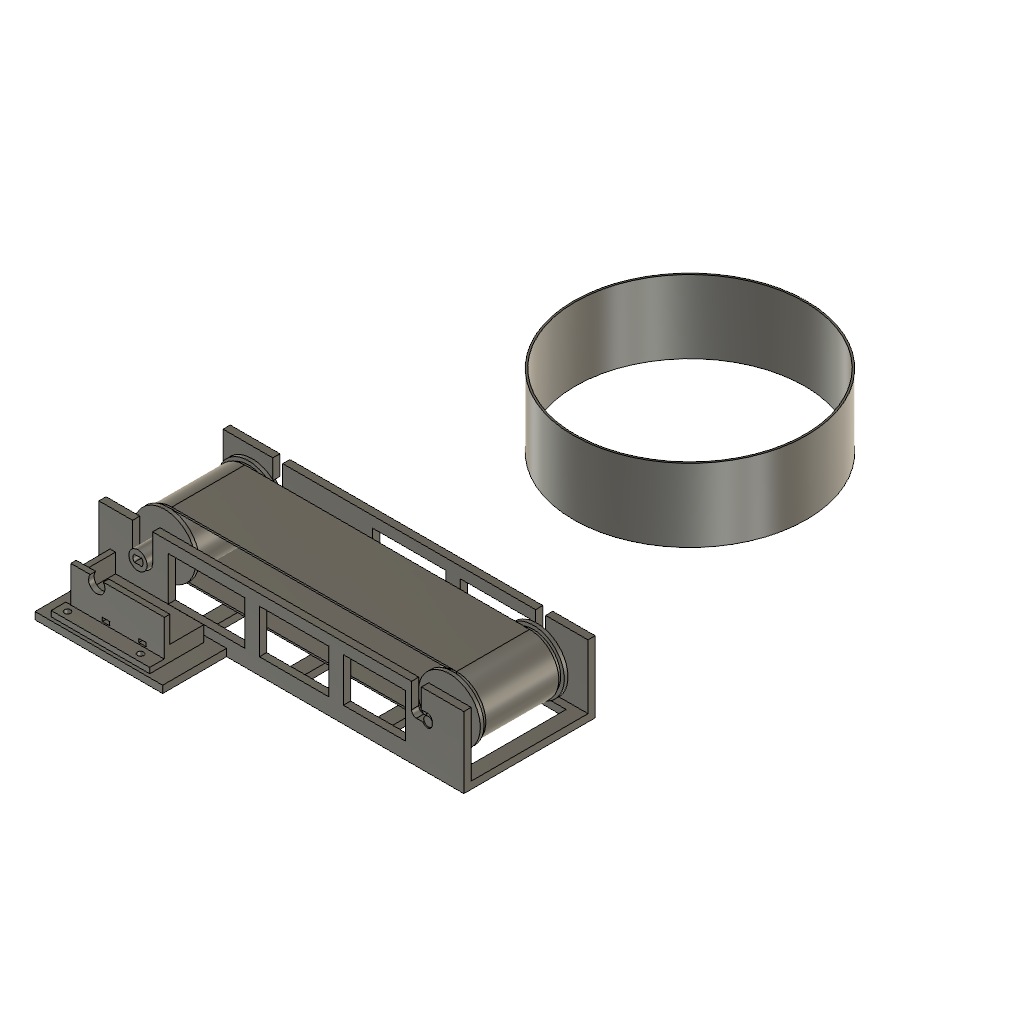
effente_conveyor (Autodesk Fusion 360 design; units mm, degrees)
part number: 2026-11-16-22-43-14-375
part number: 2026-11-16-22-43-14-555
part number: 2026-11-16-22-43-15-249
part number: 2026-11-16-22-43-15-701
part number: 2026-11-16-22-43-16-000
part number: 2026-11-16-22-43-16-313
part number: 2026-11-16-22-43-16-414
Autodesk Fusion 360 part; units mm, degrees
sketch "Sketch1" plane through (0, 0, 0) normal (0, 0, 1) x (1, 0, 0) in component "Frame"
  line L0 (0, 0) -> (200, 0)
  line L1 (200, 0) -> (200, 72)
  line L2 (200, 72) -> (0, 72)
  line L3 (0, 72) -> (0, 0)
extrude "Extrude1" add sketch "Sketch1" along normal blind 4 makes body 1 in component "Frame"
ref_plane "WorkPlane1" through (0, 0, 4) normal (0, 0, 1) x (1, 0, 0) in component "Frame"
sketch "Sketch2" plane through (0, 0, 4) normal (0, 0, 1) x (1, 0, 0) in component "Frame"
  line L0 (0, 0) -> (200, 0)
  line L1 (200, 0) -> (200, 4)
  line L2 (200, 4) -> (0, 4)
  line L3 (0, 4) -> (0, 0)
extrude "Extrude2" add sketch "Sketch2" along normal blind 35 bodies 1 in component "Frame"
ref_plane "WorkPlane2" through (0, 0, 4) normal (0, 0, 1) x (1, 0, 0) in component "Frame"
sketch "Sketch3" plane through (0, 0, 4) normal (0, 0, 1) x (1, 0, 0) in component "Frame"
  line L0 (0, 68) -> (200, 68)
  line L1 (200, 68) -> (200, 72)
  line L2 (200, 72) -> (0, 72)
  line L3 (0, 72) -> (0, 68)
extrude "Extrude3" add sketch "Sketch3" along normal blind 35 bodies 1 in component "Frame"
sketch "Sketch4" plane through (0, 0, 0) normal (0, 0, 1) x (1, 0, 0) in component "Frame"
  line L0 (0, -35) -> (70, -35)
  line L1 (70, -35) -> (70, 0.5)
  line L2 (70, 0.5) -> (0, 0.5)
  line L3 (0, 0.5) -> (0, -35)
extrude "Extrude4" add sketch "Sketch4" along normal blind 4 bodies 1 in component "Frame"
ref_plane "WorkPlane3" through (0, 2, 0) normal (0, 1, 0) x (0, 0, 1) in component "Frame"
sketch "Sketch5" plane through (0, 2, 0) normal (0, 1, 0) x (1, 0, 0) in component "Frame"
  line L0 (38, -9) -> (80, -9)
  line L1 (80, -9) -> (80, -33)
  line L2 (80, -33) -> (38, -33)
  line L3 (38, -33) -> (38, -9)
extrude "Extrude5" cut sketch "Sketch5" along normal mid plane 5 bodies 1 in component "Frame"
ref_plane "WorkPlane4" through (0, 2, 0) normal (0, 1, 0) x (0, 0, 1) in component "Frame"
sketch "Sketch6" plane through (0, 2, 0) normal (0, 1, 0) x (1, 0, 0) in component "Frame"
  line L0 (88, -9) -> (126, -9)
  line L1 (126, -9) -> (126, -33)
  line L2 (126, -33) -> (88, -33)
  line L3 (88, -33) -> (88, -9)
extrude "Extrude6" cut sketch "Sketch6" along normal mid plane 5 bodies 1 in component "Frame"
ref_plane "WorkPlane5" through (0, 2, 0) normal (0, 1, 0) x (0, 0, 1) in component "Frame"
sketch "Sketch7" plane through (0, 2, 0) normal (0, 1, 0) x (1, 0, 0) in component "Frame"
  line L0 (134, -9) -> (168, -9)
  line L1 (168, -9) -> (168, -33)
  line L2 (168, -33) -> (134, -33)
  line L3 (134, -33) -> (134, -9)
extrude "Extrude7" cut sketch "Sketch7" along normal mid plane 5 bodies 1 in component "Frame"
ref_plane "WorkPlane6" through (0, 70, 0) normal (0, 1, 0) x (0, 0, 1) in component "Frame"
sketch "Sketch8" plane through (0, 70, 0) normal (0, 1, 0) x (1, 0, 0) in component "Frame"
  line L0 (82, -9) -> (122, -9)
  line L1 (122, -9) -> (122, -33)
  line L2 (122, -33) -> (82, -33)
  line L3 (82, -33) -> (82, -9)
extrude "Extrude8" cut sketch "Sketch8" along normal mid plane 5 bodies 1 in component "Frame"
ref_plane "WorkPlane7" through (0, 70, 0) normal (0, 1, 0) x (0, 0, 1) in component "Frame"
sketch "Sketch9" plane through (0, 70, 0) normal (0, 1, 0) x (1, 0, 0) in component "Frame"
  line L0 (130, -9) -> (168, -9)
  line L1 (168, -9) -> (168, -33)
  line L2 (168, -33) -> (130, -33)
  line L3 (130, -33) -> (130, -9)
extrude "Extrude9" cut sketch "Sketch9" along normal mid plane 5 bodies 1 in component "Frame"
ref_plane "WorkPlane8" through (0, 0, -0.5) normal (0, 0, 1) x (1, 0, 0) in component "Frame"
sketch "Sketch10" plane through (0, 0, -0.5) normal (0, 0, 1) x (1, 0, 0) in component "Frame"
  line L0 (8, 8) -> (48, 8)
  line L1 (48, 8) -> (48, 64)
  line L2 (48, 64) -> (8, 64)
  line L3 (8, 64) -> (8, 8)
extrude "Extrude10" cut sketch "Sketch10" along normal blind 5 bodies 1 in component "Frame"
ref_plane "WorkPlane9" through (0, 0, -0.5) normal (0, 0, 1) x (1, 0, 0) in component "Frame"
sketch "Sketch11" plane through (0, 0, -0.5) normal (0, 0, 1) x (1, 0, 0) in component "Frame"
  line L0 (56, 8) -> (96, 8)
  line L1 (96, 8) -> (96, 64)
  line L2 (96, 64) -> (56, 64)
  line L3 (56, 64) -> (56, 8)
extrude "Extrude11" cut sketch "Sketch11" along normal blind 5 bodies 1 in component "Frame"
ref_plane "WorkPlane10" through (0, 0, -0.5) normal (0, 0, 1) x (1, 0, 0) in component "Frame"
sketch "Sketch12" plane through (0, 0, -0.5) normal (0, 0, 1) x (1, 0, 0) in component "Frame"
  line L0 (104, 8) -> (144, 8)
  line L1 (144, 8) -> (144, 64)
  line L2 (144, 64) -> (104, 64)
  line L3 (104, 64) -> (104, 8)
extrude "Extrude12" cut sketch "Sketch12" along normal blind 5 bodies 1 in component "Frame"
ref_plane "WorkPlane11" through (0, 0, -0.5) normal (0, 0, 1) x (1, 0, 0) in component "Frame"
sketch "Sketch13" plane through (0, 0, -0.5) normal (0, 0, 1) x (1, 0, 0) in component "Frame"
  line L0 (152, 8) -> (192, 8)
  line L1 (192, 8) -> (192, 64)
  line L2 (192, 64) -> (152, 64)
  line L3 (152, 64) -> (152, 8)
extrude "Extrude13" cut sketch "Sketch13" along normal blind 5 bodies 1 in component "Frame"
ref_plane "WorkPlane12" through (0, 70, 0) normal (0, 1, 0) x (0, 0, 1) in component "Frame"
sketch "Sketch14" plane through (0, 70, 0) normal (0, 1, 0) x (1, 0, 0) in component "Frame"
  circle A0 centre (24, -24) radius 2.7
extrude "Extrude14" cut sketch "Sketch14" along normal mid plane 5 bodies 1 in component "Frame"
ref_plane "WorkPlane13" through (0, 70, 0) normal (0, 1, 0) x (0, 0, 1) in component "Frame"
sketch "Sketch15" plane through (0, 70, 0) normal (0, 1, 0) x (1, 0, 0) in component "Frame"
  line L0 (24, -22.8) -> (30, -22.8)
  line L1 (30, -22.8) -> (30, -28.2)
  line L2 (30, -28.2) -> (24, -28.2)
  line L3 (24, -28.2) -> (24, -22.8)
extrude "Extrude15" cut sketch "Sketch15" along normal mid plane 5 bodies 1 in component "Frame"
ref_plane "WorkPlane14" through (0, 70, 0) normal (0, 1, 0) x (0, 0, 1) in component "Frame"
sketch "Sketch16" plane through (0, 70, 0) normal (0, 1, 0) x (1, 0, 0) in component "Frame"
  circle A0 centre (24, -25.5) radius 2.7
extrude "Extrude16" cut sketch "Sketch16" along normal mid plane 5 bodies 1 in component "Frame"
ref_plane "WorkPlane15" through (0, 70, 0) normal (0, 1, 0) x (0, 0, 1) in component "Frame"
sketch "Sketch17" plane through (0, 70, 0) normal (0, 1, 0) x (1, 0, 0) in component "Frame"
  circle A0 centre (30, -25.5) radius 2.7
extrude "Extrude17" cut sketch "Sketch17" along normal mid plane 5 bodies 1 in component "Frame"
ref_plane "WorkPlane16" through (0, 70, 0) normal (0, 1, 0) x (0, 0, 1) in component "Frame"
sketch "Sketch18" plane through (0, 70, 0) normal (0, 1, 0) x (1, 0, 0) in component "Frame"
  line L0 (27.3, -25.5) -> (32.7, -25.5)
  line L1 (32.7, -25.5) -> (32.7, -40)
  line L2 (32.7, -40) -> (27.3, -40)
  line L3 (27.3, -40) -> (27.3, -25.5)
extrude "Extrude18" cut sketch "Sketch18" along normal mid plane 5 bodies 1 in component "Frame"
ref_plane "WorkPlane17" through (0, 2, 0) normal (0, 1, 0) x (0, 0, 1) in component "Frame"
sketch "Sketch19" plane through (0, 2, 0) normal (0, 1, 0) x (1, 0, 0) in component "Frame"
  circle A0 centre (180, -24) radius 2.7
extrude "Extrude19" cut sketch "Sketch19" along normal mid plane 5 bodies 1 in component "Frame"
ref_plane "WorkPlane18" through (0, 2, 0) normal (0, 1, 0) x (0, 0, 1) in component "Frame"
sketch "Sketch20" plane through (0, 2, 0) normal (0, 1, 0) x (1, 0, 0) in component "Frame"
  line L0 (174, -22.8) -> (180, -22.8)
  line L1 (180, -22.8) -> (180, -28.2)
  line L2 (180, -28.2) -> (174, -28.2)
  line L3 (174, -28.2) -> (174, -22.8)
extrude "Extrude20" cut sketch "Sketch20" along normal mid plane 5 bodies 1 in component "Frame"
ref_plane "WorkPlane19" through (0, 2, 0) normal (0, 1, 0) x (0, 0, 1) in component "Frame"
sketch "Sketch21" plane through (0, 2, 0) normal (0, 1, 0) x (1, 0, 0) in component "Frame"
  circle A0 centre (180, -25.5) radius 2.7
extrude "Extrude21" cut sketch "Sketch21" along normal mid plane 5 bodies 1 in component "Frame"
ref_plane "WorkPlane20" through (0, 2, 0) normal (0, 1, 0) x (0, 0, 1) in component "Frame"
sketch "Sketch22" plane through (0, 2, 0) normal (0, 1, 0) x (1, 0, 0) in component "Frame"
  circle A0 centre (174, -25.5) radius 2.7
extrude "Extrude22" cut sketch "Sketch22" along normal mid plane 5 bodies 1 in component "Frame"
ref_plane "WorkPlane21" through (0, 2, 0) normal (0, 1, 0) x (0, 0, 1) in component "Frame"
sketch "Sketch23" plane through (0, 2, 0) normal (0, 1, 0) x (1, 0, 0) in component "Frame"
  line L0 (171.3, -25.5) -> (176.7, -25.5)
  line L1 (176.7, -25.5) -> (176.7, -40)
  line L2 (176.7, -40) -> (171.3, -40)
  line L3 (171.3, -40) -> (171.3, -25.5)
extrude "Extrude23" cut sketch "Sketch23" along normal mid plane 5 bodies 1 in component "Frame"
ref_plane "WorkPlane22" through (0, 70, 0) normal (0, 1, 0) x (0, 0, 1) in component "Frame"
sketch "Sketch24" plane through (0, 70, 0) normal (0, 1, 0) x (1, 0, 0) in component "Frame"
  circle A0 centre (180, -24) radius 2.7
extrude "Extrude24" cut sketch "Sketch24" along normal mid plane 5 bodies 1 in component "Frame"
ref_plane "WorkPlane23" through (0, 70, 0) normal (0, 1, 0) x (0, 0, 1) in component "Frame"
sketch "Sketch25" plane through (0, 70, 0) normal (0, 1, 0) x (1, 0, 0) in component "Frame"
  line L0 (174, -22.8) -> (180, -22.8)
  line L1 (180, -22.8) -> (180, -28.2)
  line L2 (180, -28.2) -> (174, -28.2)
  line L3 (174, -28.2) -> (174, -22.8)
extrude "Extrude25" cut sketch "Sketch25" along normal mid plane 5 bodies 1 in component "Frame"
ref_plane "WorkPlane24" through (0, 70, 0) normal (0, 1, 0) x (0, 0, 1) in component "Frame"
sketch "Sketch26" plane through (0, 70, 0) normal (0, 1, 0) x (1, 0, 0) in component "Frame"
  circle A0 centre (180, -25.5) radius 2.7
extrude "Extrude26" cut sketch "Sketch26" along normal mid plane 5 bodies 1 in component "Frame"
ref_plane "WorkPlane25" through (0, 70, 0) normal (0, 1, 0) x (0, 0, 1) in component "Frame"
sketch "Sketch27" plane through (0, 70, 0) normal (0, 1, 0) x (1, 0, 0) in component "Frame"
  circle A0 centre (174, -25.5) radius 2.7
extrude "Extrude27" cut sketch "Sketch27" along normal mid plane 5 bodies 1 in component "Frame"
ref_plane "WorkPlane26" through (0, 70, 0) normal (0, 1, 0) x (0, 0, 1) in component "Frame"
sketch "Sketch28" plane through (0, 70, 0) normal (0, 1, 0) x (1, 0, 0) in component "Frame"
  line L0 (171.3, -25.5) -> (176.7, -25.5)
  line L1 (176.7, -25.5) -> (176.7, -40)
  line L2 (176.7, -40) -> (171.3, -40)
  line L3 (171.3, -40) -> (171.3, -25.5)
extrude "Extrude28" cut sketch "Sketch28" along normal mid plane 5 bodies 1 in component "Frame"
ref_plane "WorkPlane27" through (0, 2, 0) normal (0, 1, 0) x (0, 0, 1) in component "Frame"
sketch "Sketch29" plane through (0, 2, 0) normal (0, 1, 0) x (1, 0, 0) in component "Frame"
  line L0 (18.5, -24) -> (29.5, -24)
  line L1 (29.5, -24) -> (29.5, -40)
  line L2 (29.5, -40) -> (18.5, -40)
  line L3 (18.5, -40) -> (18.5, -24)
extrude "Extrude29" cut sketch "Sketch29" along normal mid plane 5 bodies 1 in component "Frame"
ref_plane "WorkPlane28" through (0, 2, 0) normal (0, 1, 0) x (0, 0, 1) in component "Frame"
sketch "Sketch30" plane through (0, 2, 0) normal (0, 1, 0) x (1, 0, 0) in component "Frame"
  circle A0 centre (24, -24) radius 5.5
extrude "Extrude30" cut sketch "Sketch30" along normal mid plane 5 bodies 1 in component "Frame"
ref_plane "WorkPlane29" through (0, 0, -0.5) normal (0, 0, 1) x (1, 0, 0) in component "Frame"
sketch "Sketch31" plane through (0, 0, -0.5) normal (0, 0, 1) x (1, 0, 0) in component "Frame"
  circle A0 centre (12, -29.1) radius 1.7
extrude "Extrude31" cut sketch "Sketch31" along normal blind 5 bodies 1 in component "Frame"
ref_plane "WorkPlane30" through (0, 0, -0.5) normal (0, 0, 1) x (1, 0, 0) in component "Frame"
sketch "Sketch32" plane through (0, 0, -0.5) normal (0, 0, 1) x (1, 0, 0) in component "Frame"
  line L0 (15.2332, -29.1) -> (13.6166, -26.3)
  line L1 (13.6166, -26.3) -> (10.3834, -26.3)
  line L2 (10.3834, -26.3) -> (8.7668, -29.1)
  line L3 (8.7668, -29.1) -> (10.3834, -31.9)
  line L4 (10.3834, -31.9) -> (13.6166, -31.9)
  line L5 (13.6166, -31.9) -> (15.2332, -29.1)
extrude "Extrude32" cut sketch "Sketch32" along normal blind 3 bodies 1 in component "Frame"
ref_plane "WorkPlane31" through (0, 0, -0.5) normal (0, 0, 1) x (1, 0, 0) in component "Frame"
sketch "Sketch33" plane through (0, 0, -0.5) normal (0, 0, 1) x (1, 0, 0) in component "Frame"
  circle A0 centre (52, -29.1) radius 1.7
extrude "Extrude33" cut sketch "Sketch33" along normal blind 5 bodies 1 in component "Frame"
ref_plane "WorkPlane32" through (0, 0, -0.5) normal (0, 0, 1) x (1, 0, 0) in component "Frame"
sketch "Sketch34" plane through (0, 0, -0.5) normal (0, 0, 1) x (1, 0, 0) in component "Frame"
  line L0 (55.2332, -29.1) -> (53.6166, -26.3)
  line L1 (53.6166, -26.3) -> (50.3834, -26.3)
  line L2 (50.3834, -26.3) -> (48.7668, -29.1)
  line L3 (48.7668, -29.1) -> (50.3834, -31.9)
  line L4 (50.3834, -31.9) -> (53.6166, -31.9)
  line L5 (53.6166, -31.9) -> (55.2332, -29.1)
extrude "Extrude34" cut sketch "Sketch34" along normal blind 3 bodies 1 in component "Frame"
ref_plane "WorkPlane33" through (0, 71.25, 0) normal (0, 1, 0) x (0, 0, 1) in component "Frame"
sketch "Sketch35" plane through (0, 71.25, 0) normal (0, 1, 0) x (1, 0, 0) in component "Frame"
  circle A0 centre (60, -24) radius 10.05
extrude "Extrude35" cut sketch "Sketch35" along normal mid plane 2.5 bodies 1 in component "Frame"
ref_plane "WorkPlane1" through (0, 36, 0) normal (0, 1, 0) x (0, 0, 1) in component "Drive roller"
sketch "Sketch1 (2)" plane through (0, 36, 0) normal (0, 1, 0) x (1, 0, 0) in component "Drive roller"
  circle A0 centre (24, -24) radius 15
extrude "Extrude1'" add sketch "Sketch1 (2)" along normal mid plane 44 separate body makes body 2 in component "Drive roller"
ref_plane "WorkPlane2" through (0, 13, 0) normal (0, 1, 0) x (0, 0, 1) in component "Drive roller"
sketch "Sketch2 (2)" plane through (0, 13, 0) normal (0, 1, 0) x (1, 0, 0) in component "Drive roller"
  circle A0 centre (24, -24) radius 17
extrude "Extrude2'" add sketch "Sketch2 (2)" along normal mid plane 2 bodies 2 in component "Drive roller"
ref_plane "WorkPlane3" through (0, 59, 0) normal (0, 1, 0) x (0, 0, 1) in component "Drive roller"
sketch "Sketch3 (2)" plane through (0, 59, 0) normal (0, 1, 0) x (1, 0, 0) in component "Drive roller"
  circle A0 centre (24, -24) radius 17
extrude "Extrude3'" add sketch "Sketch3 (2)" along normal mid plane 2 bodies 2 in component "Drive roller"
ref_plane "WorkPlane4" through (0, 63.75, 0) normal (0, 1, 0) x (0, 0, 1) in component "Drive roller"
sketch "Sketch4 (2)" plane through (0, 63.75, 0) normal (0, 1, 0) x (1, 0, 0) in component "Drive roller"
  circle A0 centre (24, -24) radius 5
extrude "Extrude4'" add sketch "Sketch4 (2)" along normal mid plane 7.5 bodies 2 in component "Drive roller"
ref_plane "WorkPlane5" through (0, 69.5, 0) normal (0, 1, 0) x (0, 0, 1) in component "Drive roller"
sketch "Sketch5 (2)" plane through (0, 69.5, 0) normal (0, 1, 0) x (1, 0, 0) in component "Drive roller"
  circle A0 centre (24, -24) radius 2.5
extrude "Extrude5'" add sketch "Sketch5 (2)" along normal mid plane 4 bodies 2 in component "Drive roller"
ref_plane "WorkPlane6" through (0, 4.75, 0) normal (0, 1, 0) x (0, 0, 1) in component "Drive roller"
sketch "Sketch6 (2)" plane through (0, 4.75, 0) normal (0, 1, 0) x (1, 0, 0) in component "Drive roller"
  circle A0 centre (24, -24) radius 5
extrude "Extrude6'" add sketch "Sketch6 (2)" along normal mid plane 14.5 bodies 2 in component "Drive roller"
ref_plane "WorkPlane7" through (0, 1.5, 0) normal (0, 1, 0) x (0, 0, 1) in component "Drive roller"
sketch "Sketch7 (2)" plane through (0, 1.5, 0) normal (0, 1, 0) x (1, 0, 0) in component "Drive roller"
  circle A0 centre (24, -24) radius 2.8
extrude "Extrude7'" cut sketch "Sketch7 (2)" along normal mid plane 9 bodies 2 in component "Drive roller"
ref_plane "WorkPlane8" through (0, 1.75, 0) normal (0, 1, 0) x (0, 0, 1) in component "Drive roller"
sketch "Sketch8 (2)" plane through (0, 1.75, 0) normal (0, 1, 0) x (1, 0, 0) in component "Drive roller"
  line L0 (20.9, -25.925) -> (27.1, -25.925)
  line L1 (27.1, -25.925) -> (27.1, -27.1)
  line L2 (27.1, -27.1) -> (20.9, -27.1)
  line L3 (20.9, -27.1) -> (20.9, -25.925)
extrude "Extrude8'" add sketch "Sketch8 (2)" along normal mid plane 8.5 bodies 2 in component "Drive roller"
ref_plane "WorkPlane9" through (0, 1.75, 0) normal (0, 1, 0) x (0, 0, 1) in component "Drive roller"
sketch "Sketch9 (2)" plane through (0, 1.75, 0) normal (0, 1, 0) x (1, 0, 0) in component "Drive roller"
  line L0 (20.9, -20.9) -> (27.1, -20.9)
  line L1 (27.1, -20.9) -> (27.1, -22.075)
  line L2 (27.1, -22.075) -> (20.9, -22.075)
  line L3 (20.9, -22.075) -> (20.9, -20.9)
extrude "Extrude9'" add sketch "Sketch9 (2)" along normal mid plane 8.5 bodies 2 in component "Drive roller"
ref_plane "WorkPlane10" through (0, 56.25, 0) normal (0, 1, 0) x (0, 0, 1) in component "Drive roller"
sketch "Sketch10 (2)" plane through (0, 56.25, 0) normal (0, 1, 0) x (1, 0, 0) in component "Drive roller"
  circle A0 centre (34, -24) radius 1.3
extrude "Extrude10'" cut sketch "Sketch10 (2)" along normal mid plane 8.5 bodies 2 in component "Drive roller"
ref_plane "WorkPlane11" through (0, 56.25, 0) normal (0, 1, 0) x (0, 0, 1) in component "Drive roller"
sketch "Sketch11 (2)" plane through (0, 56.25, 0) normal (0, 1, 0) x (1, 0, 0) in component "Drive roller"
  circle A0 centre (24, -34) radius 1.3
extrude "Extrude11'" cut sketch "Sketch11 (2)" along normal mid plane 8.5 bodies 2 in component "Drive roller"
ref_plane "WorkPlane12" through (0, 56.25, 0) normal (0, 1, 0) x (0, 0, 1) in component "Drive roller"
sketch "Sketch12 (2)" plane through (0, 56.25, 0) normal (0, 1, 0) x (1, 0, 0) in component "Drive roller"
  circle A0 centre (14, -24) radius 1.3
extrude "Extrude12'" cut sketch "Sketch12 (2)" along normal mid plane 8.5 bodies 2 in component "Drive roller"
ref_plane "WorkPlane13" through (0, 56.25, 0) normal (0, 1, 0) x (0, 0, 1) in component "Drive roller"
sketch "Sketch13 (2)" plane through (0, 56.25, 0) normal (0, 1, 0) x (1, 0, 0) in component "Drive roller"
  circle A0 centre (24, -14) radius 1.3
extrude "Extrude13'" cut sketch "Sketch13 (2)" along normal mid plane 8.5 bodies 2 in component "Drive roller"
ref_plane "WorkPlane1" through (0, 36, 0) normal (0, 1, 0) x (0, 0, 1) in component "Idle roller"
sketch "Sketch1 (3)" plane through (0, 36, 0) normal (0, 1, 0) x (1, 0, 0) in component "Idle roller"
  circle A0 centre (180, -24) radius 15
extrude "Extrude1''" add sketch "Sketch1 (3)" along normal mid plane 44 separate body makes body 3 in component "Idle roller"
ref_plane "WorkPlane2" through (0, 13, 0) normal (0, 1, 0) x (0, 0, 1) in component "Idle roller"
sketch "Sketch2 (3)" plane through (0, 13, 0) normal (0, 1, 0) x (1, 0, 0) in component "Idle roller"
  circle A0 centre (180, -24) radius 17
extrude "Extrude2''" add sketch "Sketch2 (3)" along normal mid plane 2 bodies 3 in component "Idle roller"
ref_plane "WorkPlane3" through (0, 59, 0) normal (0, 1, 0) x (0, 0, 1) in component "Idle roller"
sketch "Sketch3 (3)" plane through (0, 59, 0) normal (0, 1, 0) x (1, 0, 0) in component "Idle roller"
  circle A0 centre (180, -24) radius 17
extrude "Extrude3''" add sketch "Sketch3 (3)" along normal mid plane 2 bodies 3 in component "Idle roller"
ref_plane "WorkPlane4" through (0, 63.75, 0) normal (0, 1, 0) x (0, 0, 1) in component "Idle roller"
sketch "Sketch4 (3)" plane through (0, 63.75, 0) normal (0, 1, 0) x (1, 0, 0) in component "Idle roller"
  circle A0 centre (180, -24) radius 5
extrude "Extrude4''" add sketch "Sketch4 (3)" along normal mid plane 7.5 bodies 3 in component "Idle roller"
ref_plane "WorkPlane5" through (0, 69.5, 0) normal (0, 1, 0) x (0, 0, 1) in component "Idle roller"
sketch "Sketch5 (3)" plane through (0, 69.5, 0) normal (0, 1, 0) x (1, 0, 0) in component "Idle roller"
  circle A0 centre (180, -24) radius 2.5
extrude "Extrude5''" add sketch "Sketch5 (3)" along normal mid plane 4 bodies 3 in component "Idle roller"
ref_plane "WorkPlane6" through (0, 8.25, 0) normal (0, 1, 0) x (0, 0, 1) in component "Idle roller"
sketch "Sketch6 (3)" plane through (0, 8.25, 0) normal (0, 1, 0) x (1, 0, 0) in component "Idle roller"
  circle A0 centre (180, -24) radius 5
extrude "Extrude6''" add sketch "Sketch6 (3)" along normal mid plane 7.5 bodies 3 in component "Idle roller"
ref_plane "WorkPlane7" through (0, 2.5, 0) normal (0, 1, 0) x (0, 0, 1) in component "Idle roller"
sketch "Sketch7 (3)" plane through (0, 2.5, 0) normal (0, 1, 0) x (1, 0, 0) in component "Idle roller"
  circle A0 centre (180, -24) radius 2.5
extrude "Extrude7''" add sketch "Sketch7 (3)" along normal mid plane 4 bodies 3 in component "Idle roller"
ref_plane "WorkPlane1" through (0, 36, 0) normal (0, 1, 0) x (0, 0, 1) in component "Belt (reference)"
sketch "Sketch1 (4)" plane through (0, 36, 0) normal (0, 1, 0) x (1, 0, 0) in component "Belt (reference)"
  circle A0 centre (24, -24) radius 16
extrude "Extrude1'''" add sketch "Sketch1 (4)" along normal mid plane 40 separate body makes body 4 in component "Belt (reference)"
ref_plane "WorkPlane2" through (0, 36, 0) normal (0, 1, 0) x (0, 0, 1) in component "Belt (reference)"
sketch "Sketch2 (4)" plane through (0, 36, 0) normal (0, 1, 0) x (1, 0, 0) in component "Belt (reference)"
  circle A0 centre (180, -24) radius 16
extrude "Extrude2'''" add sketch "Sketch2 (4)" along normal mid plane 40 bodies 4 makes body 5 in component "Belt (reference)"
ref_plane "WorkPlane3" through (0, 36, 0) normal (0, 1, 0) x (0, 0, 1) in component "Belt (reference)"
sketch "Sketch3 (4)" plane through (0, 36, 0) normal (0, 1, 0) x (1, 0, 0) in component "Belt (reference)"
  line L0 (24, -8) -> (180, -8)
  line L1 (180, -8) -> (180, -40)
  line L2 (180, -40) -> (24, -40)
  line L3 (24, -40) -> (24, -8)
extrude "Extrude3'''" add sketch "Sketch3 (4)" along normal mid plane 40 bodies 4 in component "Belt (reference)"
ref_plane "WorkPlane4" through (0, 36, 0) normal (0, 1, 0) x (0, 0, 1) in component "Belt (reference)"
sketch "Sketch4 (4)" plane through (0, 36, 0) normal (0, 1, 0) x (1, 0, 0) in component "Belt (reference)"
  circle A0 centre (24, -24) radius 15
extrude "Extrude4'''" cut sketch "Sketch4 (4)" along normal mid plane 42 bodies 4 in component "Belt (reference)"
ref_plane "WorkPlane5" through (0, 36, 0) normal (0, 1, 0) x (0, 0, 1) in component "Belt (reference)"
sketch "Sketch5 (4)" plane through (0, 36, 0) normal (0, 1, 0) x (1, 0, 0) in component "Belt (reference)"
  circle A0 centre (180, -24) radius 15
extrude "Extrude5'''" cut sketch "Sketch5 (4)" along normal mid plane 42 bodies 4 in component "Belt (reference)"
ref_plane "WorkPlane6" through (0, 36, 0) normal (0, 1, 0) x (0, 0, 1) in component "Belt (reference)"
sketch "Sketch6 (4)" plane through (0, 36, 0) normal (0, 1, 0) x (1, 0, 0) in component "Belt (reference)"
  line L0 (24, -9) -> (180, -9)
  line L1 (180, -9) -> (180, -39)
  line L2 (180, -39) -> (24, -39)
  line L3 (24, -39) -> (24, -9)
extrude "Extrude6'''" cut sketch "Sketch6 (4)" along normal mid plane 42 bodies 4 in component "Belt (reference)"
sketch "Sketch1 (5)" plane through (0, 0, 0) normal (0, 0, 1) x (1, 0, 0) in component "Belt (TPU print)"
  circle A0 centre (100, 223.8532) radius 63.8532
extrude "Extrude1''''" add sketch "Sketch1 (5)" along normal blind 40 separate body makes body 6 in component "Belt (TPU print)"
ref_plane "WorkPlane1" through (0, 0, -0.5) normal (0, 0, 1) x (1, 0, 0) in component "Belt (TPU print)"
sketch "Sketch2 (5)" plane through (0, 0, -0.5) normal (0, 0, 1) x (1, 0, 0) in component "Belt (TPU print)"
  circle A0 centre (100, 223.8532) radius 62.8532
extrude "Extrude2''''" cut sketch "Sketch2 (5)" along normal blind 41 bodies 6 in component "Belt (TPU print)"
ref_plane "WorkPlane1" through (0, 0, 4) normal (0, 0, 1) x (1, 0, 0) in component "Motor bracket"
sketch "Sketch1 (6)" plane through (0, 0, 4) normal (0, 0, 1) x (1, 0, 0) in component "Motor bracket"
  line L0 (9.7, -33.1) -> (61, -33.1)
  line L1 (61, -33.1) -> (61, -3.5)
  line L2 (61, -3.5) -> (9.7, -3.5)
  line L3 (9.7, -3.5) -> (9.7, -33.1)
extrude "Extrude1'''''" add sketch "Sketch1 (6)" along normal blind 3 separate body makes body 7 in component "Motor bracket"
ref_plane "WorkPlane2" through (0, 0, 4) normal (0, 0, 1) x (1, 0, 0) in component "Motor bracket"
sketch "Sketch2 (6)" plane through (0, 0, 4) normal (0, 0, 1) x (1, 0, 0) in component "Motor bracket"
  line L0 (7, -33.1) -> (57, -33.1)
  line L1 (57, -33.1) -> (57, -25.09)
  line L2 (57, -25.09) -> (7, -25.09)
  line L3 (7, -25.09) -> (7, -33.1)
extrude "Extrude2'''''" add sketch "Sketch2 (6)" along normal blind 3 bodies 7 in component "Motor bracket"
ref_plane "WorkPlane3" through (0, 0, 6.99) normal (0, 0, 1) x (1, 0, 0) in component "Motor bracket"
sketch "Sketch3 (5)" plane through (0, 0, 6.99) normal (0, 0, 1) x (1, 0, 0) in component "Motor bracket"
  line L0 (12.7, -22.11) -> (61, -22.11)
  line L1 (61, -22.11) -> (61, -3.5)
  line L2 (61, -3.5) -> (12.7, -3.5)
  line L3 (12.7, -3.5) -> (12.7, -22.11)
extrude "Extrude3''''" add sketch "Sketch3 (5)" along normal blind 5.46 bodies 7 in component "Motor bracket"
ref_plane "WorkPlane4" through (0, 0, 6.99) normal (0, 0, 1) x (1, 0, 0) in component "Motor bracket"
sketch "Sketch4 (5)" plane through (0, 0, 6.99) normal (0, 0, 1) x (1, 0, 0) in component "Motor bracket"
  line L0 (9.7, -25.1) -> (12.7, -25.1)
  line L1 (12.7, -25.1) -> (12.7, -3.5)
  line L2 (12.7, -3.5) -> (9.7, -3.5)
  line L3 (9.7, -3.5) -> (9.7, -25.1)
extrude "Extrude4''''" add sketch "Sketch4 (5)" along normal blind 15.76 bodies 7 in component "Motor bracket"
ref_plane "WorkPlane5" through (0, 0, 6.99) normal (0, 0, 1) x (1, 0, 0) in component "Motor bracket"
sketch "Sketch5 (5)" plane through (0, 0, 6.99) normal (0, 0, 1) x (1, 0, 0) in component "Motor bracket"
  line L0 (9.7, -25.1) -> (61, -25.1)
  line L1 (61, -25.1) -> (61, -22.1)
  line L2 (61, -22.1) -> (9.7, -22.1)
  line L3 (9.7, -22.1) -> (9.7, -25.1)
extrude "Extrude5''''" add sketch "Sketch5 (5)" along normal blind 19.76 bodies 7 in component "Motor bracket"
ref_plane "WorkPlane6" through (0, -23.6, 0) normal (0, 1, 0) x (0, 0, 1) in component "Motor bracket"
sketch "Sketch6 (5)" plane through (0, -23.6, 0) normal (0, 1, 0) x (1, 0, 0) in component "Motor bracket"
  circle A0 centre (24, -24) radius 4.5
extrude "Extrude6''''" cut sketch "Sketch6 (5)" along normal mid plane 4 bodies 7 in component "Motor bracket"
ref_plane "WorkPlane7" through (0, 0, 3.5) normal (0, 0, 1) x (1, 0, 0) in component "Motor bracket"
sketch "Sketch7 (4)" plane through (0, 0, 3.5) normal (0, 0, 1) x (1, 0, 0) in component "Motor bracket"
  circle A0 centre (12, -29.1) radius 1.7
extrude "Extrude7'''" cut sketch "Sketch7 (4)" along normal blind 4 bodies 7 in component "Motor bracket"
ref_plane "WorkPlane8" through (0, 0, 3.5) normal (0, 0, 1) x (1, 0, 0) in component "Motor bracket"
sketch "Sketch8 (3)" plane through (0, 0, 3.5) normal (0, 0, 1) x (1, 0, 0) in component "Motor bracket"
  circle A0 centre (52, -29.1) radius 1.7
extrude "Extrude8''" cut sketch "Sketch8 (3)" along normal blind 4 bodies 7 in component "Motor bracket"
ref_plane "WorkPlane9" through (0, -14.3, 0) normal (0, 1, 0) x (0, 0, 1) in component "Motor bracket"
sketch "Sketch9 (3)" plane through (0, -14.3, 0) normal (0, 1, 0) x (1, 0, 0) in component "Motor bracket"
  line L0 (27, -7.8) -> (31, -7.8)
  line L1 (31, -7.8) -> (31, -9.8)
  line L2 (31, -9.8) -> (27, -9.8)
  line L3 (27, -9.8) -> (27, -7.8)
extrude "Extrude9''" cut sketch "Sketch9 (3)" along normal mid plane 22.6 bodies 7 in component "Motor bracket"
ref_plane "WorkPlane10" through (0, -14.3, 0) normal (0, 1, 0) x (0, 0, 1) in component "Motor bracket"
sketch "Sketch10 (3)" plane through (0, -14.3, 0) normal (0, 1, 0) x (1, 0, 0) in component "Motor bracket"
  line L0 (47, -7.8) -> (51, -7.8)
  line L1 (51, -7.8) -> (51, -9.8)
  line L2 (51, -9.8) -> (47, -9.8)
  line L3 (47, -9.8) -> (47, -7.8)
extrude "Extrude10''" cut sketch "Sketch10 (3)" along normal mid plane 22.6 bodies 7 in component "Motor bracket"
component "Frame" placed x (1, 0, 0) y (0, 1, 0) z (0, 0, 1) at (0, 0, 0)
component "Drive roller" placed x (1, 0, 0) y (0, 1, 0) z (0, 0, 1) at (0, 0, 0)
component "Idle roller" placed x (1, 0, 0) y (0, 1, 0) z (0, 0, 1) at (0, 0, 0)
component "Belt (reference)" placed x (1, 0, 0) y (0, 1, 0) z (0, 0, 1) at (0, 0, 0)
component "Belt (TPU print)" placed x (1, 0, 0) y (0, 1, 0) z (0, 0, 1) at (0, 0, 0)
component "Motor bracket" placed x (1, 0, 0) y (0, 1, 0) z (0, 0, 1) at (0, 0, 0)
named bodies: "Frame", "Drive roller", "Idle roller", "Belt (reference)", "Belt (TPU print)", "Motor bracket"
